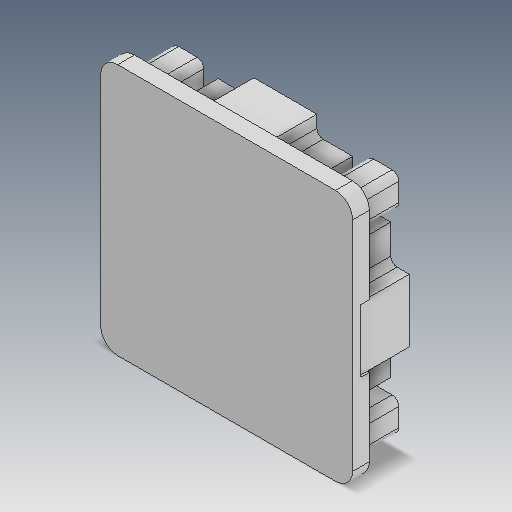
# Autodesk Inventor part: 8020_Cap
Saved by Autodesk Inventor 2025.4 (Build 294407020, 407B)
## iProperties
Created: 2026-10-18
Part Number: 8020_Cap
Material: Generic
Document SubType Name: Modeling
Designer: Aiden
Density: 1 g/cm^3
Appearance: Default
Author: Aiden
Autodesk Inventor part; units mm, degrees
ref_plane "YZ Plane" through (0, 0, 0) normal (1, 0, 0) x (0, 1, 0)
ref_plane "XZ Plane" through (0, 0, 0) normal (0, 1, 0) x (-1, 0, 0)
ref_plane "XY Plane" through (0, 0, 0) normal (0, 0, 1) x (1, 0, 0)
sketch "Sketch1" plane through (0, 0, 0) normal (0, 0, 1) x (1, 0, 0)
  arc A0 (-6, 3.9968) -> (-6.1464, 4.3504) centre (-6.5, 3.9968) ccw projected
  line L0 (-6, -3.9968) -> (-6, 3.9968) projected
  arc A1 (-6.1464, -4.3504) -> (-6, -3.9968) centre (-6.5, -3.9968) ccw projected
  line L1 (-9.9171, -8.1211) -> (-6.1464, -4.3504) projected
  arc A2 (-10.2707, -8.2675) -> (-9.9171, -8.1211) centre (-10.2707, -7.7675) ccw projected
  line L2 (-12.29, -8.2675) -> (-10.2707, -8.2675) projected
  arc A3 (-12.79, -7.7675) -> (-12.29, -8.2675) centre (-12.29, -7.7675) ccw projected
  line L3 (-12.79, -4.5) -> (-12.79, -7.7675) projected
  arc A4 (-12.79, -4.5) -> (-13.29, -4) centre (-13.29, -4.5) ccw projected
  line L4 (-14.5, -4) -> (-13.29, -4) projected
  line L5 (-14.5, -4.5) -> (-14.5, -4) projected
  line L6 (-15, -4.5) -> (-14.5, -4.5) projected
  line L7 (-15, -12.968) -> (-15, -4.5) construction
  arc A5 (-15, -12.968) -> (-12.968, -15) centre (-12.968, -12.968) ccw construction
  line L8 (-4.5, -15) -> (-12.968, -15) construction
  line L9 (-4.5, -14.5) -> (-4.5, -15) projected
  line L10 (-4, -14.5) -> (-4.5, -14.5) projected
  line L11 (-4, -13.29) -> (-4, -14.5) projected
  arc A6 (-4, -13.29) -> (-4.5, -12.79) centre (-4.5, -13.29) ccw projected
  line L12 (-7.7675, -12.79) -> (-4.5, -12.79) projected
  arc A7 (-8.2675, -12.29) -> (-7.7675, -12.79) centre (-7.7675, -12.29) ccw projected
  line L13 (-8.2675, -10.2707) -> (-8.2675, -12.29) projected
  arc A8 (-8.1211, -9.9171) -> (-8.2675, -10.2707) centre (-7.7675, -10.2707) ccw projected
  line L14 (-4.3504, -6.1464) -> (-8.1211, -9.9171) projected
  arc A9 (-3.9968, -6) -> (-4.3504, -6.1464) centre (-3.9968, -6.5) ccw projected
  line L15 (3.9968, -6) -> (-3.9968, -6) projected
  arc A10 (4.3504, -6.1464) -> (3.9968, -6) centre (3.9968, -6.5) ccw projected
  line L16 (8.1211, -9.9171) -> (4.3504, -6.1464) projected
  arc A11 (8.2675, -10.2707) -> (8.1211, -9.9171) centre (7.7675, -10.2707) ccw projected
  line L17 (8.2675, -12.29) -> (8.2675, -10.2707) projected
  arc A12 (7.7675, -12.79) -> (8.2675, -12.29) centre (7.7675, -12.29) ccw projected
  line L18 (4.5, -12.79) -> (7.7675, -12.79) projected
  arc A13 (4.5, -12.79) -> (4, -13.29) centre (4.5, -13.29) ccw projected
  line L19 (4, -14.5) -> (4, -13.29) projected
  line L20 (4.5, -14.5) -> (4, -14.5) projected
  line L21 (4.5, -15) -> (4.5, -14.5) projected
  line L22 (12.968, -15) -> (4.5, -15) construction
  arc A14 (12.968, -15) -> (15, -12.968) centre (12.968, -12.968) ccw construction
  line L23 (15, -4.5) -> (15, -12.968) construction
  line L24 (14.5, -4.5) -> (15, -4.5) projected
  line L25 (14.5, -4) -> (14.5, -4.5) projected
  line L26 (13.29, -4) -> (14.5, -4) projected
  arc A15 (13.29, -4) -> (12.79, -4.5) centre (13.29, -4.5) ccw projected
  line L27 (12.79, -7.7675) -> (12.79, -4.5) projected
  arc A16 (12.29, -8.2675) -> (12.79, -7.7675) centre (12.29, -7.7675) ccw projected
  line L28 (10.2707, -8.2675) -> (12.29, -8.2675) projected
  arc A17 (9.9171, -8.1211) -> (10.2707, -8.2675) centre (10.2707, -7.7675) ccw projected
  line L29 (6.1464, -4.3504) -> (9.9171, -8.1211) projected
  arc A18 (6, -3.9968) -> (6.1464, -4.3504) centre (6.5, -3.9968) ccw projected
  line L30 (6, 3.9968) -> (6, -3.9968) projected
  arc A19 (6.1464, 4.3504) -> (6, 3.9968) centre (6.5, 3.9968) ccw projected
  line L31 (9.9171, 8.1211) -> (6.1464, 4.3504) projected
  arc A20 (10.2707, 8.2675) -> (9.9171, 8.1211) centre (10.2707, 7.7675) ccw projected
  line L32 (12.29, 8.2675) -> (10.2707, 8.2675) projected
  arc A21 (12.79, 7.7675) -> (12.29, 8.2675) centre (12.29, 7.7675) ccw projected
  line L33 (12.79, 4.5) -> (12.79, 7.7675) projected
  arc A22 (12.79, 4.5) -> (13.29, 4) centre (13.29, 4.5) ccw projected
  line L34 (14.5, 4) -> (13.29, 4) projected
  line L35 (14.5, 4.5) -> (14.5, 4) projected
  line L36 (15, 4.5) -> (14.5, 4.5) projected
  line L37 (15, 12.968) -> (15, 4.5) construction
  arc A23 (15, 12.968) -> (12.968, 15) centre (12.968, 12.968) ccw construction
  line L38 (4.5, 15) -> (12.968, 15) construction
  line L39 (4.5, 14.5) -> (4.5, 15) projected
  line L40 (4, 14.5) -> (4.5, 14.5) projected
  line L41 (4, 13.29) -> (4, 14.5) projected
  arc A24 (4, 13.29) -> (4.5, 12.79) centre (4.5, 13.29) ccw projected
  line L42 (7.7675, 12.79) -> (4.5, 12.79) projected
  arc A25 (8.2675, 12.29) -> (7.7675, 12.79) centre (7.7675, 12.29) ccw projected
  line L43 (8.2675, 10.2707) -> (8.2675, 12.29) projected
  arc A26 (8.1211, 9.9171) -> (8.2675, 10.2707) centre (7.7675, 10.2707) ccw projected
  line L44 (4.3504, 6.1464) -> (8.1211, 9.9171) projected
  arc A27 (3.9968, 6) -> (4.3504, 6.1464) centre (3.9968, 6.5) ccw projected
  line L45 (-3.9968, 6) -> (3.9968, 6) projected
  arc A28 (-4.3504, 6.1464) -> (-3.9968, 6) centre (-3.9968, 6.5) ccw projected
  line L46 (-8.1211, 9.9171) -> (-4.3504, 6.1464) projected
  arc A29 (-8.2675, 10.2707) -> (-8.1211, 9.9171) centre (-7.7675, 10.2707) ccw projected
  line L47 (-8.2675, 12.29) -> (-8.2675, 10.2707) projected
  arc A30 (-7.7675, 12.79) -> (-8.2675, 12.29) centre (-7.7675, 12.29) ccw projected
  line L48 (-4.5, 12.79) -> (-7.7675, 12.79) projected
  arc A31 (-4.5, 12.79) -> (-4, 13.29) centre (-4.5, 13.29) ccw projected
  line L49 (-4, 14.5) -> (-4, 13.29) projected
  line L50 (-4.5, 14.5) -> (-4, 14.5) projected
  line L51 (-4.5, 15) -> (-4.5, 14.5) projected
  line L52 (-12.968, 15) -> (-4.5, 15) construction
  arc A32 (-12.968, 15) -> (-15, 12.968) centre (-12.968, 12.968) ccw construction
  line L53 (-15, 4.5) -> (-15, 12.968) construction
  line L54 (-14.5, 4.5) -> (-15, 4.5) projected
  line L55 (-14.5, 4) -> (-14.5, 4.5) projected
  line L56 (-13.29, 4) -> (-14.5, 4) projected
  arc A33 (-13.29, 4) -> (-12.79, 4.5) centre (-13.29, 4.5) ccw projected
  line L57 (-12.79, 7.7675) -> (-12.79, 4.5) projected
  arc A34 (-12.29, 8.2675) -> (-12.79, 7.7675) centre (-12.29, 7.7675) ccw projected
  line L58 (-10.2707, 8.2675) -> (-12.29, 8.2675) projected
  arc A35 (-9.9171, 8.1211) -> (-10.2707, 8.2675) centre (-10.2707, 7.7675) ccw projected
  line L59 (-6.1464, 4.3504) -> (-9.9171, 8.1211) projected
  line L60 (-3.1568, -4.5038) -> (-1.5303, -3.1477) projected
  arc A36 (-4.5038, -3.1568) -> (-3.1568, -4.5038) centre (0, 0) ccw projected
  line L61 (-3.1477, -1.5303) -> (-4.5038, -3.1568) projected
  arc A37 (-3.1477, 1.5303) -> (-3.1477, -1.5303) centre (0, 0) ccw projected
  line L62 (-4.5038, 3.1568) -> (-3.1477, 1.5303) projected
  arc A38 (-3.1568, 4.5038) -> (-4.5038, 3.1568) centre (0, 0) ccw projected
  line L63 (-1.5303, 3.1477) -> (-3.1568, 4.5038) projected
  arc A39 (1.5303, 3.1477) -> (-1.5303, 3.1477) centre (0, 0) ccw projected
  line L64 (3.1568, 4.5038) -> (1.5303, 3.1477) projected
  arc A40 (4.5038, 3.1568) -> (3.1568, 4.5038) centre (0, 0) ccw projected
  line L65 (3.1477, 1.5303) -> (4.5038, 3.1568) projected
  arc A41 (3.1477, -1.5303) -> (3.1477, 1.5303) centre (0, 0) ccw projected
  line L66 (4.5038, -3.1568) -> (3.1477, -1.5303) projected
  arc A42 (3.1568, -4.5038) -> (4.5038, -3.1568) centre (0, 0) ccw projected
  line L67 (1.5303, -3.1477) -> (3.1568, -4.5038) projected
  arc A43 (-1.5303, -3.1477) -> (1.5303, -3.1477) centre (0, 0) ccw projected
  line L68 (-12.705, -13.705) -> (-10.5135, -13.705) projected
  arc A44 (-13.705, -12.705) -> (-12.705, -13.705) centre (-12.705, -12.705) ccw projected
  line L69 (-13.705, -10.5135) -> (-13.705, -12.705) projected
  arc A45 (-12.705, -9.5135) -> (-13.705, -10.5135) centre (-12.705, -10.5135) ccw projected
  line L70 (-10.5135, -9.5135) -> (-12.705, -9.5135) projected
  arc A46 (-9.5135, -10.5135) -> (-10.5135, -9.5135) centre (-10.5135, -10.5135) ccw projected
  line L71 (-9.5135, -12.705) -> (-9.5135, -10.5135) projected
  arc A47 (-10.5135, -13.705) -> (-9.5135, -12.705) centre (-10.5135, -12.705) ccw projected
  line L72 (13.705, -12.705) -> (13.705, -10.5135) projected
  arc A48 (12.705, -13.705) -> (13.705, -12.705) centre (12.705, -12.705) ccw projected
  line L73 (10.5135, -13.705) -> (12.705, -13.705) projected
  arc A49 (9.5135, -12.705) -> (10.5135, -13.705) centre (10.5135, -12.705) ccw projected
  line L74 (9.5135, -10.5135) -> (9.5135, -12.705) projected
  arc A50 (10.5135, -9.5135) -> (9.5135, -10.5135) centre (10.5135, -10.5135) ccw projected
  line L75 (12.705, -9.5135) -> (10.5135, -9.5135) projected
  arc A51 (13.705, -10.5135) -> (12.705, -9.5135) centre (12.705, -10.5135) ccw projected
  line L76 (12.705, 13.705) -> (10.5135, 13.705) projected
  arc A52 (13.705, 12.705) -> (12.705, 13.705) centre (12.705, 12.705) ccw projected
  line L77 (13.705, 10.5135) -> (13.705, 12.705) projected
  arc A53 (12.705, 9.5135) -> (13.705, 10.5135) centre (12.705, 10.5135) ccw projected
  line L78 (10.5135, 9.5135) -> (12.705, 9.5135) projected
  arc A54 (9.5135, 10.5135) -> (10.5135, 9.5135) centre (10.5135, 10.5135) ccw projected
  line L79 (9.5135, 12.705) -> (9.5135, 10.5135) projected
  arc A55 (10.5135, 13.705) -> (9.5135, 12.705) centre (10.5135, 12.705) ccw projected
  line L80 (-13.705, 12.705) -> (-13.705, 10.5135) projected
  arc A56 (-12.705, 13.705) -> (-13.705, 12.705) centre (-12.705, 12.705) ccw projected
  line L81 (-10.5135, 13.705) -> (-12.705, 13.705) projected
  arc A57 (-9.5135, 12.705) -> (-10.5135, 13.705) centre (-10.5135, 12.705) ccw projected
  line L82 (-9.5135, 10.5135) -> (-9.5135, 12.705) projected
  arc A58 (-10.5135, 9.5135) -> (-9.5135, 10.5135) centre (-10.5135, 10.5135) ccw projected
  line L83 (-12.705, 9.5135) -> (-10.5135, 9.5135) projected
  arc A59 (-13.705, 10.5135) -> (-12.705, 9.5135) centre (-12.705, 10.5135) ccw projected
  line L84 (4.1004, 6.25) -> (8.0175, 10.1671)
  line L85 (8.0175, 10.1671) -> (8.0175, 12.54)
  line L86 (8.0175, 12.54) -> (4.5, 12.54)
  arc A60 (3.75, 13.29) -> (4.5, 12.54) centre (4.5, 13.29) ccw
  line L87 (3.75, 13.29) -> (3.75, 14.75)
  line L88 (3.75, 14.75) -> (4.25, 14.75)
  line L89 (4.25, 14.75) -> (4.25, 15.25)
  line L90 (4.25, 15.25) -> (12.968, 15.25)
  arc A61 (15.25, 12.968) -> (12.968, 15.25) centre (12.968, 12.968) ccw
  line L91 (15.25, 12.968) -> (15.25, 4.25)
  line L92 (15.25, 4.25) -> (14.75, 4.25)
  line L93 (14.75, 4.25) -> (14.75, 3.75)
  line L94 (14.75, 3.75) -> (13.29, 3.75)
  arc A62 (12.54, 4.5) -> (13.29, 3.75) centre (13.29, 4.5) ccw
  line L95 (12.54, 4.5) -> (12.54, 8.0175)
  line L96 (12.54, 8.0175) -> (10.1671, 8.0175)
  line L97 (10.1671, 8.0175) -> (6.25, 4.1004)
  line L98 (6.25, 4.1004) -> (6.25, -4.1004)
  line L99 (6.25, -4.1004) -> (10.1671, -8.0175)
  line L100 (10.1671, -8.0175) -> (12.54, -8.0175)
  line L101 (12.54, -8.0175) -> (12.54, -4.5)
  arc A63 (13.29, -3.75) -> (12.54, -4.5) centre (13.29, -4.5) ccw
  line L102 (13.29, -3.75) -> (14.75, -3.75)
  line L103 (14.75, -3.75) -> (14.75, -4.25)
  line L104 (14.75, -4.25) -> (15.25, -4.25)
  line L105 (15.25, -4.25) -> (15.25, -12.968)
  arc A64 (12.968, -15.25) -> (15.25, -12.968) centre (12.968, -12.968) ccw
  line L106 (12.968, -15.25) -> (4.25, -15.25)
  line L107 (4.25, -15.25) -> (4.25, -14.75)
  line L108 (4.25, -14.75) -> (3.75, -14.75)
  line L109 (3.75, -14.75) -> (3.75, -13.29)
  arc A65 (4.5, -12.54) -> (3.75, -13.29) centre (4.5, -13.29) ccw
  line L110 (4.5, -12.54) -> (8.0175, -12.54)
  line L111 (8.0175, -12.54) -> (8.0175, -10.1671)
  line L112 (8.0175, -10.1671) -> (4.1004, -6.25)
  line L113 (4.1004, -6.25) -> (-4.1004, -6.25)
  line L114 (-4.1004, -6.25) -> (-8.0175, -10.1671)
  line L115 (-8.0175, -10.1671) -> (-8.0175, -12.54)
  line L116 (-8.0175, -12.54) -> (-4.5, -12.54)
  arc A66 (-3.75, -13.29) -> (-4.5, -12.54) centre (-4.5, -13.29) ccw
  line L117 (-3.75, -13.29) -> (-3.75, -14.75)
  line L118 (-3.75, -14.75) -> (-4.25, -14.75)
  line L119 (-4.25, -14.75) -> (-4.25, -15.25)
  line L120 (-4.25, -15.25) -> (-12.968, -15.25)
  arc A67 (-15.25, -12.968) -> (-12.968, -15.25) centre (-12.968, -12.968) ccw
  line L121 (-15.25, -12.968) -> (-15.25, -4.25)
  line L122 (-15.25, -4.25) -> (-14.75, -4.25)
  line L123 (-14.75, -4.25) -> (-14.75, -3.75)
  line L124 (-14.75, -3.75) -> (-13.29, -3.75)
  arc A68 (-12.54, -4.5) -> (-13.29, -3.75) centre (-13.29, -4.5) ccw
  line L125 (-12.54, -4.5) -> (-12.54, -8.0175)
  line L126 (-12.54, -8.0175) -> (-10.1671, -8.0175)
  line L127 (-10.1671, -8.0175) -> (-6.25, -4.1004)
  line L128 (-6.25, -4.1004) -> (-6.25, 4.1004)
  line L129 (-6.25, 4.1004) -> (-10.1671, 8.0175)
  line L130 (-10.1671, 8.0175) -> (-12.54, 8.0175)
  line L131 (-12.54, 8.0175) -> (-12.54, 4.5)
  arc A69 (-13.29, 3.75) -> (-12.54, 4.5) centre (-13.29, 4.5) ccw
  line L132 (-13.29, 3.75) -> (-14.75, 3.75)
  line L133 (-14.75, 3.75) -> (-14.75, 4.25)
  line L134 (-14.75, 4.25) -> (-15.25, 4.25)
  line L135 (-15.25, 4.25) -> (-15.25, 12.968)
  arc A70 (-12.968, 15.25) -> (-15.25, 12.968) centre (-12.968, 12.968) ccw
  line L136 (-12.968, 15.25) -> (-4.25, 15.25)
  line L137 (-4.25, 15.25) -> (-4.25, 14.75)
  line L138 (-4.25, 14.75) -> (-3.75, 14.75)
  line L139 (-3.75, 14.75) -> (-3.75, 13.29)
  arc A71 (-4.5, 12.54) -> (-3.75, 13.29) centre (-4.5, 13.29) ccw
  line L140 (-4.5, 12.54) -> (-8.0175, 12.54)
  line L141 (-8.0175, 12.54) -> (-8.0175, 10.1671)
  line L142 (-8.0175, 10.1671) -> (-4.1004, 6.25)
  line L143 (-4.1004, 6.25) -> (4.1004, 6.25)
  line L144 (-3.75, 14.75) -> (3.75, 14.75)
  line L145 (14.75, 3.75) -> (14.75, -3.75)
  line L146 (3.75, -14.75) -> (-3.75, -14.75)
  line L147 (-14.75, -3.75) -> (-14.75, 3.75)
  arc A72 (-9.7135, 12.705) -> (-10.5135, 13.505) centre (-10.5135, 12.705) ccw
  line L148 (-10.5135, 13.505) -> (-12.705, 13.505)
  arc A73 (-12.705, 13.505) -> (-13.505, 12.705) centre (-12.705, 12.705) ccw
  line L149 (-13.505, 12.705) -> (-13.505, 10.5135)
  arc A74 (-13.505, 10.5135) -> (-12.705, 9.7135) centre (-12.705, 10.5135) ccw
  line L150 (-12.705, 9.7135) -> (-10.5135, 9.7135)
  arc A75 (-10.5135, 9.7135) -> (-9.7135, 10.5135) centre (-10.5135, 10.5135) ccw
  line L151 (-9.7135, 10.5135) -> (-9.7135, 12.705)
  line L152 (10.5135, 9.7135) -> (12.705, 9.7135)
  arc A76 (12.705, 9.7135) -> (13.505, 10.5135) centre (12.705, 10.5135) ccw
  line L153 (13.505, 10.5135) -> (13.505, 12.705)
  arc A77 (13.505, 12.705) -> (12.705, 13.505) centre (12.705, 12.705) ccw
  line L154 (12.705, 13.505) -> (10.5135, 13.505)
  arc A78 (10.5135, 13.505) -> (9.7135, 12.705) centre (10.5135, 12.705) ccw
  line L155 (9.7135, 12.705) -> (9.7135, 10.5135)
  arc A79 (9.7135, 10.5135) -> (10.5135, 9.7135) centre (10.5135, 10.5135) ccw
  arc A80 (10.5135, -9.7135) -> (9.7135, -10.5135) centre (10.5135, -10.5135) ccw
  line L156 (9.7135, -10.5135) -> (9.7135, -12.705)
  arc A81 (9.7135, -12.705) -> (10.5135, -13.505) centre (10.5135, -12.705) ccw
  line L157 (10.5135, -13.505) -> (12.705, -13.505)
  arc A82 (12.705, -13.505) -> (13.505, -12.705) centre (12.705, -12.705) ccw
  line L158 (13.505, -12.705) -> (13.505, -10.5135)
  arc A83 (13.505, -10.5135) -> (12.705, -9.7135) centre (12.705, -10.5135) ccw
  line L159 (12.705, -9.7135) -> (10.5135, -9.7135)
  arc A84 (-13.505, -12.705) -> (-12.705, -13.505) centre (-12.705, -12.705) ccw
  line L160 (-12.705, -13.505) -> (-10.5135, -13.505)
  arc A85 (-10.5135, -13.505) -> (-9.7135, -12.705) centre (-10.5135, -12.705) ccw
  line L161 (-9.7135, -12.705) -> (-9.7135, -10.5135)
  arc A86 (-9.7135, -10.5135) -> (-10.5135, -9.7135) centre (-10.5135, -10.5135) ccw
  line L162 (-10.5135, -9.7135) -> (-12.705, -9.7135)
  arc A87 (-12.705, -9.7135) -> (-13.505, -10.5135) centre (-12.705, -10.5135) ccw
  line L163 (-13.505, -10.5135) -> (-13.505, -12.705)
  line L164 (-1.557, 2.9096) -> (-3.1656, 4.2508)
  arc A88 (-3.1656, 4.2508) -> (-4.2508, 3.1656) centre (0, 0) ccw
  line L165 (-4.2508, 3.1656) -> (-2.9096, 1.557)
  arc A89 (-2.9096, 1.557) -> (-2.9096, -1.557) centre (0, 0) ccw
  line L166 (-2.9096, -1.557) -> (-4.2508, -3.1656)
  arc A90 (-4.2508, -3.1656) -> (-3.1656, -4.2508) centre (0, 0) ccw
  line L167 (-3.1656, -4.2508) -> (-1.557, -2.9096)
  arc A91 (-1.557, -2.9096) -> (1.557, -2.9096) centre (0, 0) ccw
  line L168 (1.557, -2.9096) -> (3.1656, -4.2508)
  arc A92 (3.1656, -4.2508) -> (4.2508, -3.1656) centre (0, 0) ccw
  line L169 (4.2508, -3.1656) -> (2.9096, -1.557)
  arc A93 (2.9096, -1.557) -> (2.9096, 1.557) centre (0, 0) ccw
  line L170 (2.9096, 1.557) -> (4.2508, 3.1656)
  arc A94 (4.2508, 3.1656) -> (3.1656, 4.2508) centre (0, 0) ccw
  line L171 (3.1656, 4.2508) -> (1.557, 2.9096)
  arc A95 (1.557, 2.9096) -> (-1.557, 2.9096) centre (0, 0) ccw
  point P0 (0, 0)
  point P1 (0, 6.25)
  point P2 (0, 6)
  point P3 (11.6093, -9.7135)
  dimension "d0" = 0.25
  dimension "d1" = 0.2
  dimension "d2" = 0.2
  dimension "d3" = 0.2
  dimension "d4" = 0.2
  dimension "d5" = 0.2
  constraints: 176 end point, 72 point on circle, 36 centre point, 3 midpoint, 3 perpendicular, 1 horizontal, 114 other
  measures "d0" distance of point (0, 6.25) point (0, 6)
  measures "d1" distance between parallel lines of L83 L150
  measures "d2" distance between parallel lines of L78 L152
  measures "d3" distance from line of L75 point (11.609, -9.714)
  measures "d4" distance between parallel lines of L70 L162
  measures "d5" radial gap between concentric circles of A39 A95
extrude "Extrusion1" add sketch "Sketch1" against normal blind 5 contours L143 L142 L141 L140 A71 L139 L144 L87 A60 L86 L85 L84 | L145 L102 A63 L101 L100 L99 L98 L97 L96 L95 A62 L94 | L132 A69 L131 L130 L129 L128 L127 L126 L125 A68 L124 L147 | L146 L117 A66 L116 L115 L114 L113 L112 L111 L110 A65 L109 | L151 A75 L150 A74 L149 A73 L148 A72 | A79 L155 A78 L154 A77 L153 A76 L152 | L159 A83 L158 A82 L157 A81 L156 A80 | L163 A87 L162 A86 L161 A85 L160 A84 | A95 L171 A94 L170 A93 L169 A92 L168 A91 L167 A90 L166 A89 L165 A88 L164
sketch "Sketch3" plane through (0, 0, 0) normal (0, 0, 1) x (1, 0, 0)
  line L0 (-15, 4.5) -> (-15, 12.968) projected
  arc A0 (-12.968, 15) -> (-15, 12.968) centre (-12.968, 12.968) ccw projected
  line L1 (-12.968, 15) -> (-4.5, 15) projected
  line L2 (4.5, 15) -> (12.968, 15) projected
  arc A1 (15, 12.968) -> (12.968, 15) centre (12.968, 12.968) ccw projected
  line L3 (15, 12.968) -> (15, 4.5) projected
  line L4 (15, -4.5) -> (15, -12.968) projected
  arc A2 (12.968, -15) -> (15, -12.968) centre (12.968, -12.968) ccw projected
  line L5 (12.968, -15) -> (4.5, -15) projected
  line L6 (-4.5, -15) -> (-12.968, -15) projected
  arc A3 (-15, -12.968) -> (-12.968, -15) centre (-12.968, -12.968) ccw projected
  line L7 (-15, -12.968) -> (-15, -4.5) projected
  line L8 (-15, 4.5) -> (-15, -4.5)
  line L9 (-4.5, 15) -> (4.5, 15)
  line L10 (-3.75, 14.75) -> (3.75, 14.75) projected
  line L11 (15, 4.5) -> (15, -4.5)
  line L12 (13.29, 3.75) -> (14.75, 3.75) projected
  line L13 (4.5, -15) -> (-4.5, -15)
  line L14 (3.75, -14.75) -> (-3.75, -14.75) projected
  point P0 (0, 0)
  constraints: 8 end point, 2 parallel, 1 perpendicular
extrude "Extrusion2" add sketch "Sketch3" along normal blind 2
sketch "Sketch4" plane through (0, 0, 0) normal (0, 0, -1) x (-1, 0, 0)
  line L0 (-14.75, 3.75) -> (-14.75, -3.75) projected
  line L1 (-15, -12.968) -> (-15, 12.968) projected
  line L2 (-14.75, 3.75) -> (-15, 3.75)
  line L3 (-15, 3.75) -> (-15, -3.75)
  line L4 (-15, -3.75) -> (-14.75, -3.75)
  line L5 (-14.75, -3.75) -> (-14.75, 3.75)
  line L6 (-12.968, 15) -> (12.968, 15) projected
  line L7 (0, 15) -> (0, -15)
  line L8 (12.968, -15) -> (-12.968, -15) projected
  line L9 (14.75, 3.75) -> (14.75, -3.75)
  line L10 (15, -12.968) -> (15, 12.968)
  line L11 (14.75, 3.75) -> (15, 3.75)
  line L12 (15, 3.75) -> (15, -3.75)
  line L13 (15, -3.75) -> (14.75, -3.75)
  line L14 (14.75, -3.75) -> (14.75, 3.75)
  point P0 (0, 0)
  constraints: 22 end point, 7 symmetric about line, 2 midpoint, 2 parallel, 2 point on line, 1 horizontal, 1 horizontal alignment, 1 perpendicular
extrude "Extrusion3" cut sketch "Sketch4" against normal blind 1
body "Solid1"
